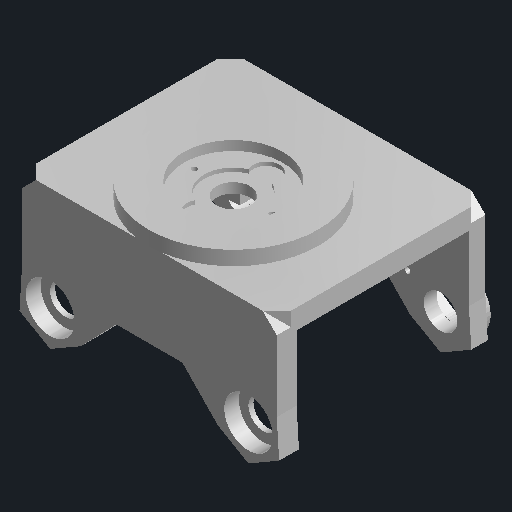
# Autodesk Inventor part: Pelvis
Saved by Autodesk Inventor 2027 (Build 310192060, 192F)
## iProperties
Part Number: Pelvis
Material: PLA (proyecto)
Document SubType Name: Modelado
Designer: rodri
Appearance: Suave - Blanco
Mass: 23.4958 g
Surface Area: 115.367 cm^2
Volume: 18.9482 cm^3
Density: 1.24 g/cm^3
Author: rodri
Autodesk Inventor part; units mm, degrees
ref_plane "Plano de trabajo1" through (0, 0, -1) normal (0, 0, 1) x (1, 0, 0)
sketch "Boceto1" plane through (0, 0, -1) normal (0, 0, 1) x (1, 0, 0)
  line L0 (24, -3) -> (27, -6)
  line L1 (27, -6) -> (27, -21)
  line L2 (27, -21) -> (27.4952, -28.75)
  line L3 (27.4952, -28.75) -> (21, -32.5)
  line L4 (21, -32.5) -> (14.5048, -28.75)
  line L5 (14.5048, -28.75) -> (7, -21)
  line L6 (7, -21) -> (-7, -21)
  line L7 (-7, -21) -> (-14.5048, -28.75)
  line L8 (-14.5048, -28.75) -> (-21, -32.5)
  line L9 (-21, -32.5) -> (-27.4952, -28.75)
  line L10 (-27.4952, -28.75) -> (-27, -21)
  line L11 (-27, -21) -> (-27, -6)
  line L12 (-27, -6) -> (-24, -3)
  line L13 (-24, -3) -> (24, -3)
  constraints: 28 end point
extrude "Extrusión1" add sketch "Boceto1" along normal blind 3.5
ref_plane "Plano de trabajo2" through (0, 0, 39) normal (0, 0, 1) x (1, 0, 0)
sketch "Boceto2" plane through (0, 0, 39) normal (0, 0, 1) x (1, 0, 0)
  line L0 (24, -3) -> (27, -6)
  line L1 (27, -6) -> (27, -21)
  line L2 (27, -21) -> (27.4952, -28.75)
  line L3 (27.4952, -28.75) -> (21, -32.5)
  line L4 (21, -32.5) -> (14.5048, -28.75)
  line L5 (14.5048, -28.75) -> (7, -21)
  line L6 (7, -21) -> (-7, -21)
  line L7 (-7, -21) -> (-14.5048, -28.75)
  line L8 (-14.5048, -28.75) -> (-21, -32.5)
  line L9 (-21, -32.5) -> (-27.4952, -28.75)
  line L10 (-27.4952, -28.75) -> (-27, -21)
  line L11 (-27, -21) -> (-27, -6)
  line L12 (-27, -6) -> (-24, -3)
  line L13 (-24, -3) -> (24, -3)
  constraints: 28 end point
extrude "Extrusión2" add sketch "Boceto2" along normal blind 4.2
ref_plane "Plano de trabajo3" through (0, -7.2, 0) normal (0, 1, 0) x (-1, 0, 0)
sketch "Boceto3" plane through (0, -7.2, 0) normal (0, 1, 0) x (-1, 0, 0)
  line L0 (24, -1) -> (-24, -1)
  line L1 (-24, -1) -> (-27, 2)
  line L2 (-27, 2) -> (-27, 40.2)
  line L3 (-27, 40.2) -> (-24, 43.2)
  line L4 (-24, 43.2) -> (24, 43.2)
  line L5 (24, 43.2) -> (27, 40.2)
  line L6 (27, 40.2) -> (27, 2)
  line L7 (27, 2) -> (24, -1)
  constraints: 16 end point
extrude "Extrusión3" add sketch "Boceto3" along normal blind 4.2
ref_plane "Plano de trabajo4" through (0, -3.01, 0) normal (0, 1, 0) x (-1, 0, 0)
sketch "Boceto4" plane through (0, -3.01, 0) normal (0, 1, 0) x (-1, 0, 0)
  circle A0 centre (0, 25.4) radius 18
  constraints: 1 centre point
extrude "Extrusión4" add sketch "Boceto4" along normal blind 3.01
ref_plane "Plano de trabajo5" through (0, -2, 0) normal (0, 1, 0) x (-1, 0, 0)
sketch "Boceto5" plane through (0, -2, 0) normal (0, 1, 0) x (-1, 0, 0)
  circle A0 centre (0, 25.4) radius 10.5
  constraints: 1 centre point
extrude "Extrusión5" cut sketch "Boceto5" along normal blind 2.1
ref_plane "Plano de trabajo6" through (0, 0, -2.2) normal (0, 0, 1) x (1, 0, 0)
sketch "Boceto6" plane through (0, 0, -2.2) normal (0, 0, 1) x (1, 0, 0)
  line L0 (2.6479, -17.006) -> (2.8029, -18.1836)
  line L1 (2.8029, -18.1836) -> (3.2575, -19.281)
  line L2 (3.2575, -19.281) -> (3.9806, -20.2233)
  line L3 (3.9806, -20.2233) -> (4.9229, -20.9464)
  line L4 (4.9229, -20.9464) -> (17.4083, -29.6808)
  line L5 (17.4083, -29.6808) -> (18.05, -30.1095)
  line L6 (18.05, -30.1095) -> (18.7422, -30.4509)
  line L7 (18.7422, -30.4509) -> (19.473, -30.699)
  line L8 (19.473, -30.699) -> (20.2299, -30.8495)
  line L9 (20.2299, -30.8495) -> (21, -30.9)
  line L10 (21, -30.9) -> (21.7701, -30.8495)
  line L11 (21.7701, -30.8495) -> (22.527, -30.699)
  line L12 (22.527, -30.699) -> (23.2578, -30.4509)
  line L13 (23.2578, -30.4509) -> (23.95, -30.1095)
  line L14 (23.95, -30.1095) -> (24.5917, -29.6808)
  line L15 (24.5917, -29.6808) -> (25.1719, -29.1719)
  line L16 (25.1719, -29.1719) -> (25.6808, -28.5917)
  line L17 (25.6808, -28.5917) -> (26.1095, -27.95)
  line L18 (26.1095, -27.95) -> (26.4509, -27.2578)
  line L19 (26.4509, -27.2578) -> (26.699, -26.527)
  line L20 (26.699, -26.527) -> (26.8495, -25.7701)
  line L21 (26.8495, -25.7701) -> (26.9, -25)
  line L22 (26.9, -25) -> (26.8495, -24.2299)
  line L23 (26.8495, -24.2299) -> (26.699, -23.473)
  line L24 (26.699, -23.473) -> (26.4509, -22.7422)
  line L25 (26.4509, -22.7422) -> (26.1095, -22.05)
  line L26 (26.1095, -22.05) -> (25.6808, -21.4083)
  line L27 (25.6808, -21.4083) -> (25.1719, -20.8281)
  line L28 (25.1719, -20.8281) -> (24.5917, -20.3192)
  line L29 (24.5917, -20.3192) -> (23.95, -19.8905)
  line L30 (23.95, -19.8905) -> (23.2578, -19.5491)
  line L31 (23.2578, -19.5491) -> (9.4729, -13.0655)
  line L32 (9.4729, -13.0655) -> (8.3755, -12.611)
  line L33 (8.3755, -12.611) -> (7.1979, -12.456)
  line L34 (7.1979, -12.456) -> (6.0203, -12.611)
  line L35 (6.0203, -12.611) -> (4.9229, -13.0655)
  line L36 (4.9229, -13.0655) -> (3.9806, -13.7886)
  line L37 (3.9806, -13.7886) -> (3.2575, -14.731)
  line L38 (3.2575, -14.731) -> (2.8029, -15.8283)
  line L39 (2.8029, -15.8283) -> (2.6479, -17.006)
  constraints: 80 end point
extrude "Extrusión6" add sketch "Boceto6" along normal blind 1.7
ref_plane "Plano de trabajo7" through (0, 0, -2.21) normal (0, 0, 1) x (1, 0, 0)
sketch "Boceto7" plane through (0, 0, -2.21) normal (0, 0, 1) x (1, 0, 0)
  line L0 (5.0479, -17.006) -> (5.1212, -17.5624)
  line L1 (5.1212, -17.5624) -> (5.336, -18.081)
  line L2 (5.336, -18.081) -> (5.6776, -18.5262)
  line L3 (5.6776, -18.5262) -> (6.1229, -18.8679)
  line L4 (6.1229, -18.8679) -> (18.8693, -27.7767)
  line L5 (18.8693, -27.7767) -> (19.25, -28.0311)
  line L6 (19.25, -28.0311) -> (19.6606, -28.2336)
  line L7 (19.6606, -28.2336) -> (20.0941, -28.3807)
  line L8 (20.0941, -28.3807) -> (20.5432, -28.4701)
  line L9 (20.5432, -28.4701) -> (21, -28.5)
  line L10 (21, -28.5) -> (21.4568, -28.4701)
  line L11 (21.4568, -28.4701) -> (21.9059, -28.3807)
  line L12 (21.9059, -28.3807) -> (22.3394, -28.2336)
  line L13 (22.3394, -28.2336) -> (22.75, -28.0311)
  line L14 (22.75, -28.0311) -> (23.1307, -27.7767)
  line L15 (23.1307, -27.7767) -> (23.4749, -27.4749)
  line L16 (23.4749, -27.4749) -> (23.7767, -27.1307)
  line L17 (23.7767, -27.1307) -> (24.0311, -26.75)
  line L18 (24.0311, -26.75) -> (24.2336, -26.3394)
  line L19 (24.2336, -26.3394) -> (24.3807, -25.9059)
  line L20 (24.3807, -25.9059) -> (24.4701, -25.4568)
  line L21 (24.4701, -25.4568) -> (24.5, -25)
  line L22 (24.5, -25) -> (24.4701, -24.5432)
  line L23 (24.4701, -24.5432) -> (24.3807, -24.0941)
  line L24 (24.3807, -24.0941) -> (24.2336, -23.6606)
  line L25 (24.2336, -23.6606) -> (24.0311, -23.25)
  line L26 (24.0311, -23.25) -> (23.7767, -22.8693)
  line L27 (23.7767, -22.8693) -> (23.4749, -22.5251)
  line L28 (23.4749, -22.5251) -> (23.1307, -22.2233)
  line L29 (23.1307, -22.2233) -> (22.75, -21.9689)
  line L30 (22.75, -21.9689) -> (22.3394, -21.7664)
  line L31 (22.3394, -21.7664) -> (8.2729, -15.144)
  line L32 (8.2729, -15.144) -> (7.7544, -14.9292)
  line L33 (7.7544, -14.9292) -> (7.1979, -14.856)
  line L34 (7.1979, -14.856) -> (6.6414, -14.9292)
  line L35 (6.6414, -14.9292) -> (6.1229, -15.144)
  line L36 (6.1229, -15.144) -> (5.6776, -15.4857)
  line L37 (5.6776, -15.4857) -> (5.336, -15.931)
  line L38 (5.336, -15.931) -> (5.1212, -16.4495)
  line L39 (5.1212, -16.4495) -> (5.0479, -17.006)
  constraints: 80 end point
extrude "Extrusión7" cut sketch "Boceto7" along normal blind 2.02
ref_plane "Plano de trabajo8" through (0, 0, -0.22) normal (0, 0, 1) x (1, 0, 0)
sketch "Boceto8" plane through (0, 0, -0.22) normal (0, 0, 1) x (1, 0, 0)
  circle A0 centre (21, -25) radius 3.55
  circle A1 centre (14.0081, -20.9504) radius 0.6
  circle A2 centre (10.5987, -18.9756) radius 0.6
  constraints: 3 centre point
extrude "Extrusión8" cut sketch "Boceto8" along normal blind 4.7
ref_plane "Plano de trabajo9" through (0, 0, -2.2) normal (0, 0, 1) x (1, 0, 0)
sketch "Boceto9" plane through (0, 0, -2.2) normal (0, 0, 1) x (1, 0, 0)
  line L0 (-26.9, -25) -> (-26.8495, -25.7701)
  line L1 (-26.8495, -25.7701) -> (-26.699, -26.527)
  line L2 (-26.699, -26.527) -> (-26.4509, -27.2578)
  line L3 (-26.4509, -27.2578) -> (-26.1095, -27.95)
  line L4 (-26.1095, -27.95) -> (-25.6808, -28.5917)
  line L5 (-25.6808, -28.5917) -> (-25.1719, -29.1719)
  line L6 (-25.1719, -29.1719) -> (-24.5917, -29.6808)
  line L7 (-24.5917, -29.6808) -> (-23.95, -30.1095)
  line L8 (-23.95, -30.1095) -> (-23.2578, -30.4509)
  line L9 (-23.2578, -30.4509) -> (-22.527, -30.699)
  line L10 (-22.527, -30.699) -> (-21.7701, -30.8495)
  line L11 (-21.7701, -30.8495) -> (-21, -30.9)
  line L12 (-21, -30.9) -> (-20.2299, -30.8495)
  line L13 (-20.2299, -30.8495) -> (-19.473, -30.699)
  line L14 (-19.473, -30.699) -> (-18.7422, -30.4509)
  line L15 (-18.7422, -30.4509) -> (-18.05, -30.1095)
  line L16 (-18.05, -30.1095) -> (-17.4083, -29.6808)
  line L17 (-17.4083, -29.6808) -> (-4.9229, -20.9464)
  line L18 (-4.9229, -20.9464) -> (-3.9806, -20.2233)
  line L19 (-3.9806, -20.2233) -> (-3.2575, -19.281)
  line L20 (-3.2575, -19.281) -> (-2.8029, -18.1836)
  line L21 (-2.8029, -18.1836) -> (-2.6479, -17.006)
  line L22 (-2.6479, -17.006) -> (-2.8029, -15.8283)
  line L23 (-2.8029, -15.8283) -> (-3.2575, -14.731)
  line L24 (-3.2575, -14.731) -> (-3.9806, -13.7886)
  line L25 (-3.9806, -13.7886) -> (-4.9229, -13.0655)
  line L26 (-4.9229, -13.0655) -> (-6.0203, -12.611)
  line L27 (-6.0203, -12.611) -> (-7.1979, -12.456)
  line L28 (-7.1979, -12.456) -> (-8.3755, -12.611)
  line L29 (-8.3755, -12.611) -> (-9.4729, -13.0655)
  line L30 (-9.4729, -13.0655) -> (-23.2578, -19.5491)
  line L31 (-23.2578, -19.5491) -> (-23.95, -19.8905)
  line L32 (-23.95, -19.8905) -> (-24.5917, -20.3192)
  line L33 (-24.5917, -20.3192) -> (-25.1719, -20.8281)
  line L34 (-25.1719, -20.8281) -> (-25.6808, -21.4083)
  line L35 (-25.6808, -21.4083) -> (-26.1095, -22.05)
  line L36 (-26.1095, -22.05) -> (-26.4509, -22.7422)
  line L37 (-26.4509, -22.7422) -> (-26.699, -23.473)
  line L38 (-26.699, -23.473) -> (-26.8495, -24.2299)
  line L39 (-26.8495, -24.2299) -> (-26.9, -25)
  constraints: 80 end point
extrude "Extrusión9" add sketch "Boceto9" along normal blind 1.7
ref_plane "Plano de trabajo10" through (0, 0, -2.21) normal (0, 0, 1) x (1, 0, 0)
sketch "Boceto10" plane through (0, 0, -2.21) normal (0, 0, 1) x (1, 0, 0)
  line L0 (-24.5, -25) -> (-24.4701, -25.4568)
  line L1 (-24.4701, -25.4568) -> (-24.3807, -25.9059)
  line L2 (-24.3807, -25.9059) -> (-24.2336, -26.3394)
  line L3 (-24.2336, -26.3394) -> (-24.0311, -26.75)
  line L4 (-24.0311, -26.75) -> (-23.7767, -27.1307)
  line L5 (-23.7767, -27.1307) -> (-23.4749, -27.4749)
  line L6 (-23.4749, -27.4749) -> (-23.1307, -27.7767)
  line L7 (-23.1307, -27.7767) -> (-22.75, -28.0311)
  line L8 (-22.75, -28.0311) -> (-22.3394, -28.2336)
  line L9 (-22.3394, -28.2336) -> (-21.9059, -28.3807)
  line L10 (-21.9059, -28.3807) -> (-21.4568, -28.4701)
  line L11 (-21.4568, -28.4701) -> (-21, -28.5)
  line L12 (-21, -28.5) -> (-20.5432, -28.4701)
  line L13 (-20.5432, -28.4701) -> (-20.0941, -28.3807)
  line L14 (-20.0941, -28.3807) -> (-19.6606, -28.2336)
  line L15 (-19.6606, -28.2336) -> (-19.25, -28.0311)
  line L16 (-19.25, -28.0311) -> (-18.8693, -27.7767)
  line L17 (-18.8693, -27.7767) -> (-6.1229, -18.8679)
  line L18 (-6.1229, -18.8679) -> (-5.6776, -18.5262)
  line L19 (-5.6776, -18.5262) -> (-5.336, -18.081)
  line L20 (-5.336, -18.081) -> (-5.1212, -17.5624)
  line L21 (-5.1212, -17.5624) -> (-5.0479, -17.006)
  line L22 (-5.0479, -17.006) -> (-5.1212, -16.4495)
  line L23 (-5.1212, -16.4495) -> (-5.336, -15.931)
  line L24 (-5.336, -15.931) -> (-5.6776, -15.4857)
  line L25 (-5.6776, -15.4857) -> (-6.1229, -15.144)
  line L26 (-6.1229, -15.144) -> (-6.6414, -14.9292)
  line L27 (-6.6414, -14.9292) -> (-7.1979, -14.856)
  line L28 (-7.1979, -14.856) -> (-7.7544, -14.9292)
  line L29 (-7.7544, -14.9292) -> (-8.2729, -15.144)
  line L30 (-8.2729, -15.144) -> (-22.3394, -21.7664)
  line L31 (-22.3394, -21.7664) -> (-22.75, -21.9689)
  line L32 (-22.75, -21.9689) -> (-23.1307, -22.2233)
  line L33 (-23.1307, -22.2233) -> (-23.4749, -22.5251)
  line L34 (-23.4749, -22.5251) -> (-23.7767, -22.8693)
  line L35 (-23.7767, -22.8693) -> (-24.0311, -23.25)
  line L36 (-24.0311, -23.25) -> (-24.2336, -23.6606)
  line L37 (-24.2336, -23.6606) -> (-24.3807, -24.0941)
  line L38 (-24.3807, -24.0941) -> (-24.4701, -24.5432)
  line L39 (-24.4701, -24.5432) -> (-24.5, -25)
  constraints: 80 end point
extrude "Extrusión10" cut sketch "Boceto10" along normal blind 2.02
ref_plane "Plano de trabajo11" through (0, 0, -0.22) normal (0, 0, 1) x (1, 0, 0)
sketch "Boceto11" plane through (0, 0, -0.22) normal (0, 0, 1) x (1, 0, 0)
  circle A0 centre (-21, -25) radius 3.55
  circle A1 centre (-14.0081, -20.9504) radius 0.6
  circle A2 centre (-10.5987, -18.9756) radius 0.6
  constraints: 3 centre point
extrude "Extrusión11" cut sketch "Boceto11" along normal blind 4.7
ref_plane "Plano de trabajo12" through (0, -7.21, 0) normal (0, 1, 0) x (-1, 0, 0)
sketch "Boceto12" plane through (0, -7.21, 0) normal (0, 1, 0) x (-1, 0, 0)
  line L0 (0.2545, 17.0667) -> (0.7462, 17.1984)
  line L1 (0.7462, 17.1984) -> (1.1871, 17.453)
  line L2 (1.1871, 17.453) -> (1.547, 17.8129)
  line L3 (1.547, 17.8129) -> (1.6887, 18.025)
  line L4 (1.6887, 18.025) -> (1.8465, 18.3732)
  line L5 (1.8465, 18.3732) -> (1.9333, 18.7455)
  line L6 (1.9333, 18.7455) -> (1.95, 19)
  line L7 (1.95, 19) -> (1.95, 22.0393)
  line L8 (1.95, 22.0393) -> (16.6545, 23.4667)
  line L9 (16.6545, 23.4667) -> (16.9047, 23.5164)
  line L10 (16.9047, 23.5164) -> (17.2625, 23.6511)
  line L11 (17.2625, 23.6511) -> (17.6857, 23.9339)
  line L12 (17.6857, 23.9339) -> (18.0214, 24.3166)
  line L13 (18.0214, 24.3166) -> (18.2016, 24.6538)
  line L14 (18.2016, 24.6538) -> (18.3333, 25.1455)
  line L15 (18.3333, 25.1455) -> (18.3458, 25.5275)
  line L16 (18.3458, 25.5275) -> (18.2836, 25.9047)
  line L17 (18.2836, 25.9047) -> (18.1489, 26.2625)
  line L18 (18.1489, 26.2625) -> (17.8661, 26.6857)
  line L19 (17.8661, 26.6857) -> (17.4834, 27.0214)
  line L20 (17.4834, 27.0214) -> (17.1462, 27.2016)
  line L21 (17.1462, 27.2016) -> (16.6545, 27.3333)
  line L22 (16.6545, 27.3333) -> (1.95, 28.7607)
  line L23 (1.95, 28.7607) -> (1.9458, 31.9275)
  line L24 (1.9458, 31.9275) -> (1.9125, 32.1804)
  line L25 (1.9125, 32.1804) -> (1.8016, 32.5462)
  line L26 (1.8016, 32.5462) -> (1.547, 32.9871)
  line L27 (1.547, 32.9871) -> (1.2857, 33.2661)
  line L28 (1.2857, 33.2661) -> (1.0834, 33.4214)
  line L29 (1.0834, 33.4214) -> (0.7462, 33.6016)
  line L30 (0.7462, 33.6016) -> (0.5047, 33.6836)
  line L31 (0.5047, 33.6836) -> (0, 33.75)
  line L32 (0, 33.75) -> (-0.5047, 33.6836)
  line L33 (-0.5047, 33.6836) -> (-0.8625, 33.5489)
  line L34 (-0.8625, 33.5489) -> (-1.0834, 33.4214)
  line L35 (-1.0834, 33.4214) -> (-1.4661, 33.0857)
  line L36 (-1.4661, 33.0857) -> (-1.6214, 32.8834)
  line L37 (-1.6214, 32.8834) -> (-1.8016, 32.5462)
  line L38 (-1.8016, 32.5462) -> (-1.8836, 32.3047)
  line L39 (-1.8836, 32.3047) -> (-1.9458, 31.9275)
  line L40 (-1.9458, 31.9275) -> (-1.95, 28.7607)
  line L41 (-1.95, 28.7607) -> (-16.6545, 27.3333)
  line L42 (-16.6545, 27.3333) -> (-17.0268, 27.2465)
  line L43 (-17.0268, 27.2465) -> (-17.4834, 27.0214)
  line L44 (-17.4834, 27.0214) -> (-17.8661, 26.6857)
  line L45 (-17.8661, 26.6857) -> (-18.1489, 26.2625)
  line L46 (-18.1489, 26.2625) -> (-18.2836, 25.9047)
  line L47 (-18.2836, 25.9047) -> (-18.3458, 25.5275)
  line L48 (-18.3458, 25.5275) -> (-18.3333, 25.1455)
  line L49 (-18.3333, 25.1455) -> (-18.2016, 24.6538)
  line L50 (-18.2016, 24.6538) -> (-18.0214, 24.3166)
  line L51 (-18.0214, 24.3166) -> (-17.6857, 23.9339)
  line L52 (-17.6857, 23.9339) -> (-17.375, 23.7113)
  line L53 (-17.375, 23.7113) -> (-16.9047, 23.5164)
  line L54 (-16.9047, 23.5164) -> (-16.6545, 23.4667)
  line L55 (-16.6545, 23.4667) -> (-1.95, 22.0393)
  line L56 (-1.95, 22.0393) -> (-1.9458, 18.8725)
  line L57 (-1.9458, 18.8725) -> (-1.9125, 18.6196)
  line L58 (-1.9125, 18.6196) -> (-1.8016, 18.2538)
  line L59 (-1.8016, 18.2538) -> (-1.6214, 17.9166)
  line L60 (-1.6214, 17.9166) -> (-1.4661, 17.7143)
  line L61 (-1.4661, 17.7143) -> (-1.2857, 17.5339)
  line L62 (-1.2857, 17.5339) -> (-0.975, 17.3113)
  line L63 (-0.975, 17.3113) -> (-0.7462, 17.1984)
  line L64 (-0.7462, 17.1984) -> (-0.3804, 17.0875)
  line L65 (-0.3804, 17.0875) -> (-0.1275, 17.0542)
  line L66 (-0.1275, 17.0542) -> (0.2545, 17.0667)
  constraints: 134 end point
extrude "Extrusión12" cut sketch "Boceto12" along normal blind 2.32
ref_plane "Plano de trabajo13" through (0, -4.92, 0) normal (0, 1, 0) x (-1, 0, 0)
sketch "Boceto13" plane through (0, -4.92, 0) normal (0, 1, 0) x (-1, 0, 0)
  circle A0 centre (0, 25.4) radius 3.55
  constraints: 1 centre point
extrude "Extrusión13" cut sketch "Boceto13" along normal blind 10
ref_plane "Plano de trabajo14" through (0, -4.92, 0) normal (0, 1, 0) x (-1, 0, 0)
sketch "Boceto14" plane through (0, -4.92, 0) normal (0, 1, 0) x (-1, 0, 0)
  circle A0 centre (-8.24, 25.4) radius 0.6
  circle A1 centre (-12.08, 25.4) radius 0.6
  circle A2 centre (8.24, 25.4) radius 0.6
  circle A3 centre (12.08, 25.4) radius 0.6
  constraints: 4 centre point
extrude "Extrusión14" cut sketch "Boceto14" along normal blind 3
ref_plane "Plano de trabajo15" through (0, -2.8, 0) normal (0, 1, 0) x (-1, 0, 0)
sketch "Boceto15" plane through (0, -2.8, 0) normal (0, 1, 0) x (-1, 0, 0)
  circle A0 centre (0, 25.4) radius 6.2
  constraints: 1 centre point
extrude "Extrusión15" cut sketch "Boceto15" along normal blind 5
ref_plane "Plano de trabajo16" through (0, -2.8, 0) normal (0, 1, 0) x (-1, 0, 0)
sketch "Boceto16" plane through (0, -2.8, 0) normal (0, 1, 0) x (-1, 0, 0)
  circle A0 centre (0, 32.4) radius 2.8
  circle A1 centre (0, 18.4) radius 2.8
  constraints: 2 centre point
extrude "Extrusión16" cut sketch "Boceto16" along normal blind 5
ref_plane "Plano de trabajo17" through (0, 0, 38.9) normal (0, 0, 1) x (1, 0, 0)
sketch "Boceto17" plane through (0, 0, 38.9) normal (0, 0, 1) x (1, 0, 0)
  circle A0 centre (21, -25) radius 3.15
  circle A1 centre (-21, -25) radius 3.15
  constraints: 2 centre point
extrude "Extrusión17" cut sketch "Boceto17" along normal blind 4.4
ref_plane "Plano de trabajo18" through (0, 0, 40.075) normal (0, 0, 1) x (1, 0, 0)
sketch "Boceto18" plane through (0, 0, 40.075) normal (0, 0, 1) x (1, 0, 0)
  circle A0 centre (21, -25) radius 5.15
  circle A1 centre (-21, -25) radius 5.15
  constraints: 2 centre point
extrude "Extrusión18" cut sketch "Boceto18" along normal blind 3.225
ref_plane "Plano de trabajo19" through (0, 0, -1.1) normal (0, 0, 1) x (1, 0, 0)
sketch "Boceto19" plane through (0, 0, -1.1) normal (0, 0, 1) x (1, 0, 0)
  line L0 (10.5, -13.4) -> (13.5, -13.4)
  line L1 (13.5, -13.4) -> (13.5, -11.8)
  line L2 (13.5, -11.8) -> (10.5, -11.8)
  line L3 (10.5, -11.8) -> (10.5, -13.4)
  line L4 (10.5, -6.2) -> (13.5, -6.2)
  line L5 (13.5, -6.2) -> (13.5, -4.6)
  line L6 (13.5, -4.6) -> (10.5, -4.6)
  line L7 (10.5, -4.6) -> (10.5, -6.2)
  line L8 (-13.5, -13.4) -> (-10.5, -13.4)
  line L9 (-10.5, -13.4) -> (-10.5, -11.8)
  line L10 (-10.5, -11.8) -> (-13.5, -11.8)
  line L11 (-13.5, -11.8) -> (-13.5, -13.4)
  line L12 (-13.5, -6.2) -> (-10.5, -6.2)
  line L13 (-10.5, -6.2) -> (-10.5, -4.6)
  line L14 (-10.5, -4.6) -> (-13.5, -4.6)
  line L15 (-13.5, -4.6) -> (-13.5, -6.2)
  constraints: 32 end point, 8 parallel, 4 horizontal, 4 perpendicular
extrude "Extrusión19" cut sketch "Boceto19" along normal blind 3.7
